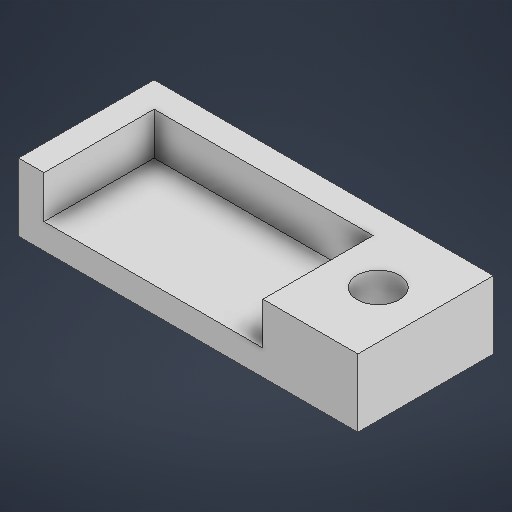
# Autodesk Inventor part: 2_08_plaque_servomot
Saved by Autodesk Inventor 2026 (Build 300175000, 175)
## iProperties
Created: 2025-06-08
Part Number: 2_08_plaque_servomot
Material: Générique
Document SubType Name: Modeling
Designer: Diogo
Density: 1 g/cm^3
Appearance: Par défaut
Author: Diogo
Autodesk Inventor part; units mm, degrees
ref_plane "YZ Plane" through (0, 0, 0) normal (1, 0, 0) x (0, 1, 0)
ref_plane "XZ Plane" through (0, 0, 0) normal (0, 1, 0) x (-1, 0, 0)
ref_plane "XY Plane" through (0, 0, 0) normal (0, 0, 1) x (1, 0, 0)
sketch "Esquisse1" plane through (0, 0, 0) normal (0, 1, 0) x (-1, 0, 0)
  line L0 (0, 0) -> (40.05, 0)
  line L1 (40.05, 0) -> (40.05, -16)
  line L2 (40.05, -16) -> (0, -16)
  line L3 (0, -16) -> (0, 0)
  dimension "d0" = 40.05
  dimension "d1" = 16
  constraints: 8 end point, 2 parallel, 1 horizontal, 1 perpendicular
  measures "d0" distance of L1.end L2.end
  measures "d1" distance of L0.end L1.end
extrude "Extrusion1" add sketch "Esquisse1" along normal blind 3
sketch "Esquisse2" plane through (0, 3, 0) normal (0, 1, 0) x (1, 0, 0)
  line L0 (-40.05, 16) -> (-40.05, 0) construction
  line L1 (-40.05, 0) -> (-37.05, 0) construction
  line L2 (-37.05, 0) -> (-37.05, 23.1134) construction
  line L3 (-37.05, 23.1134) -> (-40.05, 23.1134) construction
  line L4 (-40.05, 23.1134) -> (-40.05, 0) construction
  line L5 (0, 16) -> (-40.05, 16) construction
  line L6 (-40.05, 16) -> (-6.3328, 16) construction
  line L7 (-6.3328, 16) -> (-6.3328, 13) construction
  line L8 (-40.05, 13) -> (-40.05, 16) construction
  line L9 (-40.05, 16) -> (-37.05, 16)
  line L10 (-37.05, 13) -> (-37.05, 0)
  line L11 (-37.05, 0) -> (-40.05, 0)
  line L12 (-40.05, 0) -> (-40.05, 16)
  line L13 (-40.05, 0) -> (0, 0) projected
  line L14 (0, 0) -> (-11.2, 0)
  line L15 (-11.2, 0) -> (-11.2, 13)
  line L16 (0, 13) -> (0, 0)
  line L17 (-37.05, 16) -> (0, 16)
  line L18 (0, 16) -> (0, 13)
  line L19 (-11.2, 13) -> (-37.05, 13)
  line L20 (-6.3328, 13) -> (0, 13) construction
  line L21 (-11.2, 13) -> (-40.05, 13) construction
  point P0 (-11.2, 0)
  dimension "d4" = 3
  dimension "d5" = 3
  dimension "d6" = 11.2
  constraints: 38 end point, 9 parallel, 5 horizontal, 5 perpendicular
  measures "d4" distance of L3.end L2.end
  measures "d5" distance of L6.end L7.end
  measures "d6" distance of L15.end L16.start
extrude "Extrusion2" add sketch "Esquisse2" along normal blind 5 contours L9 L17 L18 L16 L13 L15 L19 L10 L11 L12
sketch "Esquisse3" plane through (0, 8, 0) normal (0, 1, 0) x (1, 0, 0)
  line L0 (-11.2, 13) -> (-11.2, 0) projected
  line L1 (-11.2, 0) -> (0, 0) projected
  point P0 (-5.6, 8)
  dimension "d9" = 5.6
  dimension "d10" = 8
  measures "d9" distance from line of L0 point (-5.6, 8)
  measures "d10" distance from line of L1 point (-5.6, 8)
hole "Perçage1" at (-5.6, 8, -8) direction (0, -1, 0) diameter 5 depth 3.5 tip angle 118
